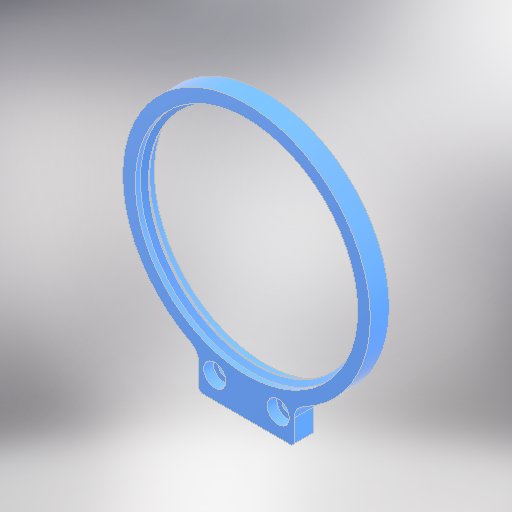
# Autodesk Inventor part: 3D_loader-pitch
Saved by Autodesk Inventor 2025.3 (Build 293356030, 356C)
## iProperties
Created: 2026-05-31
Part Number: 3D_loader-pitch
Material: 一般
Document SubType Name: Modeling
Designer: ibuki_ono
Density: 1 g/cm^3
Appearance: 滑らか - 黒
Author: ibuki_ono
## iProperties of the stored document 3D_loader-pitch_3D プリント.ipt
Created: 2026-06-10
Part Number: 3D_loader-pitch_3D プリント
Material: 一般
Document SubType Name: Modeling
Designer: ibuki_ono
Density: 1 g/cm^3
Appearance: 既定
Author: ibuki_ono
Autodesk Inventor part; units mm, degrees
ref_plane "YZ Plane" through (0, 0, 0) normal (1, 0, 0) x (0, 1, 0)
ref_plane "XZ Plane" through (0, 0, 0) normal (0, 1, 0) x (-1, 0, 0)
ref_plane "XY Plane" through (0, 0, 0) normal (0, 0, 1) x (1, 0, 0)
sketch "スケッチ1" plane through (0, 0, 0) normal (0, 0, 1) x (1, 0, 0)
  circle A0 centre (0, 0) radius 35
  circle A1 centre (0, 0) radius 39
  dimension "d0" = 70
  dimension "d2" = 4
  constraints: 2 centre point, 1 coincident
  measures "d0" diameter of A0
  measures "d2" radial gap between concentric circles of A0 A1
extrude "押し出し1" add sketch "スケッチ1" along normal mid plane 6
sketch "スケッチ2" plane through (0, 0, -3) normal (0, 0, -1) x (-1, 0, 0)
  circle A0 centre (0, 0) radius 39 projected
  line L0 (-15, -36) -> (15, -36)
  line L1 (15, -36) -> (15, -47)
  line L2 (15, -47) -> (-15, -47)
  line L3 (-15, -47) -> (-15, -36)
  point P0 (0, -36)
  dimension "d5" = 30
  dimension "d6" = 47
  constraints: 8 end point, 2 parallel, 1 horizontal, 1 midpoint, 1 perpendicular, 1 vertical alignment, 2 other
  measures "d5" distance of L1.end L2.end
  measures "d6" distance from line of point (0, 0) L2
extrude "押し出し2" add sketch "スケッチ2" against normal up to surface (6 mm away) contours A0 L1 L2 L3
sketch "スケッチ4" plane through (0, 0, 3) normal (0, 0, 1) x (1, 0, 0)
  line L0 (-15, -47) -> (-15, -36) projected
  line L1 (15, -36) -> (15, -47) projected
  line L2 (-15, -40) -> (15, -40) construction
  line L3 (15, -47) -> (-15, -47) construction
  point P0 (0, 0)
  point P1 (-10, -40)
  point P2 (10, -40)
  dimension "d19" = 7
  dimension "d20" = 5
  dimension "d21" = 5
  constraints: 4 point on line, 2 end point, 1 perpendicular
  measures "d19" distance between parallel lines of L3 L2
  measures "d20" distance from line of L0 point (-10, -40)
  measures "d21" distance from line of L1 point (10, -40)
hole "穴2" at (-10, -40, 3) at (10, -40, 3) direction (0, 0, -1) diameter 3.5 end through all counterbore diameter 7 counterbore depth 3
fillet "フィレット1" radius 5 4 edges at (-15, -36, -1.5) (-15, -36, 1.5) (15, -36, -1.5) (15, -36, 1.5)
sketch "スケッチ5" plane through (0, 0, 0) normal (1, 0, 0) x (0, 1, 0)
  line L0 (35, 3) -> (35, -3) projected
  line L1 (35, -1.425) -> (33.575, 0)
  line L2 (33.575, 0) -> (35, 1.425)
  line L3 (0, -4.2) -> (0, 4.2) projected
  point P0 (0, 0)
  point P1 (35, 0)
  dimension "d30" = 2.85
  dimension "d31" = 45
  dimension "d32" = 45
  constraints: 4 end point, 2 point on line, 1 horizontal alignment, 1 midpoint
  measures "d30" distance of L2.end L1.start
  measures "d31" angle of L0 L1
  measures "d32" angle of L0 L2
revolve "回転1" add sketch "スケッチ5" angle 360 about axis through (0, 0, -10) along (0, 0, 1)
chamfer "面取り1" distance 0.2 angle 45 1 edges at (0, -33.575, 0)
chamfer "面取り2" distance 0.8 angle 45 2 edges at (15, -47, 0) (-15, -47, 0)
equation "\"d21\" = d20"
equation "\"d32\" = d31"
